helga (vbQN_gmW) (Autodesk Fusion 360 design; units mm, degrees)
Autodesk Fusion 360 part; units mm, degrees
sketch "Sketch1" plane through (0, 0, 0) normal (0, 1, 0) x (1, 0, 0)
  line L0 (-18.8529, -6.608) -> (-18.8529, 6.7072)
  line L1 (-18.8529, 6.7072) -> (-13.5404, 6.7072)
  line L2 (-13.5404, 6.7072) -> (-13.5404, 9.306)
  line L3 (-13.5404, 9.306) -> (-10.8692, 9.306)
  line L4 (-10.8692, 9.306) -> (-10.8692, 14.6796)
  line L5 (-10.8692, 14.6796) -> (-8.1875, 14.6796)
  line L6 (-8.1875, 14.6796) -> (-8.1875, 17.4084)
  line L7 (-8.1875, 17.4084) -> (-2.8745, 17.4084)
  line L8 (-2.8745, 17.4084) -> (-2.8745, 20.1089)
  line L9 (-2.8745, 20.1089) -> (13.211, 20.1089)
  line L10 (13.211, 20.1089) -> (13.211, 17.4084)
  line L11 (21.2891, -9.3556) -> (21.2891, -12.059)
  line L12 (21.2891, -12.059) -> (18.5792, -12.059)
  line L13 (18.5792, -12.059) -> (18.5792, -14.682)
  line L14 (18.5792, -14.682) -> (15.9015, -14.682)
  line L15 (15.9015, -14.682) -> (15.9015, -17.4193)
  line L16 (15.9015, -17.4193) -> (13.2066, -17.4193)
  line L17 (-2.8389, -17.4193) -> (-8.1595, -17.4193)
  line L18 (-10.8692, 9.306) -> (-10.8657, -14.7405)
  line L19 (-18.8529, -6.608) -> (23.8924, -6.608)
  line L20 (-13.5404, 6.7072) -> (-13.5404, -9.665)
  line L21 (21.2891, -9.3556) -> (-13.5404, -9.3556)
  line L22 (18.5792, -12.059) -> (-10.8661, -12.059)
  line L23 (15.9015, -14.682) -> (-15.6391, -14.682)
  line L24 (13.2066, -17.4193) -> (-2.8389, -17.4193)
  line L25 (-8.1875, 14.6796) -> (-8.1875, -20.5391)
  line L26 (21.2891, -9.3556) -> (21.2891, 15.6129)
  line L27 (18.5792, -12.059) -> (18.5792, 18)
  line L28 (-8.1875, 14.6796) -> (23.3304, 14.6796)
  line L29 (-2.8745, 17.4084) -> (23.633, 17.4084)
  line L30 (15.9015, -14.682) -> (15.9015, 21.5634)
  line L31 (13.2066, -17.4193) -> (13.211, 17.4084)
  line L32 (-2.8745, 17.4084) -> (-2.8745, -22)
  line L33 (13.2066, -17.4193) -> (13.2088, -20.0387)
  line L34 (13.2088, -20.0387) -> (-3.2969, -20.0524)
  line L35 (21.2891, -9.3556) -> (23.9084, -9.3556)
  line L36 (-10.8692, 9.306) -> (27.1159, 9.306)
  line L37 (23.9084, -9.3556) -> (23.9084, 10.661)
  line L38 (21.2891, 12.0886) -> (-11.4104, 12.0886)
  line L39 (-13.5404, 6.7072) -> (25.3004, 6.7072)
  line L40 (-18.8529, -3.9765) -> (23.9084, -3.9765)
  line L41 (-16.2077, -1.3461) -> (-18.8529, -1.3461)
  line L42 (-16.2077, -1.3461) -> (25.3213, -1.3461)
  line L43 (-16.166, 1.3788) -> (-18.8529, 1.3788)
  line L44 (-16.166, 1.3788) -> (24.817, 1.3788)
  line L45 (-16.144, 3.9482) -> (-18.8529, 3.9482)
  line L46 (-16.144, 3.9482) -> (24.3622, 3.9482)
  line L47 (-16.144, 3.9482) -> (-16.144, 7.2291)
  line L48 (-16.144, 3.9482) -> (-16.166, -6.9315)
  line L49 (0, 0) -> (0.0167, -20.0497)
  line L50 (0, 0) -> (0, 20.1089)
  line L51 (-5.4992, -17.4193) -> (-5.531, 17.4084)
  line L52 (2.5197, -6.608) -> (2.5309, -20.0476)
  line L53 (2.5197, -6.608) -> (2.5197, 20.1089)
  line L54 (2.5309, -20.0476) -> (5.3487, -20.0452)
  line L55 (5.3487, -20.0452) -> (5.3487, 20.1089)
  line L56 (5.3487, -20.0452) -> (8.2373, -20.0428)
  line L57 (8.2373, -20.0428) -> (8.2373, 20.1089)
  line L58 (10.5159, -3.9765) -> (10.5159, -20.0452)
  line L59 (10.5159, -3.9765) -> (10.5159, 20.1089)
  line L60 (-16.1654, -6.608) -> (-13.5404, -9.3556)
  line L61 (-13.5404, -9.3556) -> (-10.8661, -12.059)
  line L62 (-10.8657, -14.7405) -> (-8.1595, -17.4193)
  line L63 (-5.4992, -17.4193) -> (-5.4989, -17.6947)
  line L64 (-5.4992, -17.4193) -> (-2.8745, -20.0521)
  line L65 (13.2088, -20.0387) -> (15.9015, -17.4193)
  line L66 (15.9015, -17.4193) -> (18.5792, -14.682)
  line L67 (18.5792, -14.682) -> (21.2891, -12.059)
  line L68 (21.2891, -12.059) -> (23.9084, -9.3556)
  line L69 (23.9084, 9.306) -> (21.2891, 12.0886)
  line L70 (21.2891, 12.0886) -> (18.5792, 14.6796)
  line L71 (18.5792, 14.6796) -> (15.9015, 17.4084)
  line L72 (15.9015, 17.4084) -> (13.211, 20.1089)
  line L73 (-2.8745, 20.1089) -> (-5.531, 17.4084)
  line L74 (-8.1875, 17.4084) -> (-10.8692, 14.6796)
  line L75 (-10.8692, 12.0886) -> (-13.5404, 9.306)
  line L76 (-13.5404, 9.306) -> (-16.144, 6.7072)
  dimension "d6" = 31.5406
  constraint vertical L0
  constraint perpendicular L0 L1
  constraint perpendicular L1 L2
  constraint perpendicular L2 L3
  constraint perpendicular L3 L4
  constraint perpendicular L4 L5
  constraint perpendicular L5 L6
  constraint perpendicular L6 L7
  constraint perpendicular L7 L8
  constraint perpendicular L8 L9
  constraint perpendicular L9 L10
  constraint perpendicular L11 L12
  constraint perpendicular L12 L13
  constraint perpendicular L13 L14
  constraint perpendicular L14 L15
  constraint perpendicular L15 L16
  constraint perpendicular L19 L20
  constraint coincident L20 L21.end
  constraint perpendicular L20 L21
  constraint coincident L18 L22.end
  constraint perpendicular L13 L22
  constraint horizontal L23
  constraint perpendicular L17 L25
  constraint perpendicular L21 L26
  constraint perpendicular L26 L28
  constraint perpendicular L27 L29
  constraint perpendicular L29 L30
  constraint perpendicular L33 L34
  constraint perpendicular L26 L35
  constraint horizontal L36
  constraint perpendicular L36 L37
  constraint coincident L26 L38.start
  constraint perpendicular L4 L38
  constraint perpendicular L37 L39
  constraint coincident L0 L40.start
  constraint coincident L37 L40.end
  constraint perpendicular L37 L40
  constraint coincident L0 L41.end
  constraint perpendicular L0 L41
  constraint perpendicular L37 L42
  constraint coincident L0 L43.end
  constraint perpendicular L0 L43
  constraint perpendicular L37 L44
  constraint coincident L0 L45.end
  constraint perpendicular L0 L45
  constraint perpendicular L37 L46
  constraint perpendicular L1 L47
  constraint coincident L49.start L50.start
  constraint coincident L34 L49.end
  constraint perpendicular L34 L49
  constraint coincident L9 L50.end
  constraint perpendicular L9 L50
  constraint midpoint L17 L51.start
  constraint midpoint L7 L51.end
  constraint midpoint L19 L52.start
  constraint coincident L34 L52.end
  constraint perpendicular L34 L52
  constraint coincident L9 L53.end
  constraint perpendicular L9 L53
  constraint coincident L34 L54.end
  constraint coincident L9 L55.end
  constraint perpendicular L9 L55
  constraint coincident L34 L56.end
  constraint parallel L34 L56
  constraint coincident L9 L57.end
  constraint perpendicular L9 L57
  constraint coincident L40 L58.start
  constraint perpendicular L24 L58
  constraint coincident L9 L59.end
  constraint perpendicular L9 L59
  constraint coincident L48 L60.start
  constraint coincident L19 L60.start
  constraint coincident L34 L64.end
  constraint coincident L32 L64.end
  constraint coincident L36 L69.start
  constraint coincident L37 L69.start
  constraint coincident L28 L70.end
  constraint coincident L27 L70.end
  constraint coincident L30 L71.end
  constraint coincident L29 L71.end
  constraint coincident L4 L75.start
  constraint coincident L38 L75.start
  constraint coincident L47 L76.end
  constraint coincident L1 L76.end
  measures "d6" distance of L14.end L23.end
extrude "Extrude1" add sketch "Sketch1" along normal blind 4 contours L20 L40 L42 L48 | L18 L20 L40 L42 | L18 L19 L21 L25 | L18 L19 L25 L40 | L18 L25 L40 L42 | L20 L44 L46 L48 | L19 L25 L40 L51 | L19 L21 L25 L51 | L21 L22 L25 L51 | L22 L23 L25 L51 | L18 L20 L44 L46 | L18 L25 L42 L44 | L25 L40 L42 L51 | L19 L32 L40 L51 | L19 L21 L32 L51 | L21 L22 L32 L51 | L22 L23 L32 L51 | L18 L25 L44 L46 | L25 L42 L44 L51 | L32 L40 L42 L51 | L19 L32 L40 L49 | L19 L21 L32 L49 | L21 L22 L32 L49 | L22 L23 L32 L49 | L18 L25 L39 L46 | L25 L44 L46 L51 | L32 L42 L44 L51 | L32 L40 L42 L49 | L19 L40 L49 L53 | L19 L21 L49 L52 | L21 L22 L49 L52 | L17 L23 L24 L32 L49 | L22 L23 L49 L52 | L18 L25 L36 L39 | L25 L39 L46 L51 | L32 L44 L46 L51 | L32 L42 L44 L49 L50 | L19 L21 L52 L55 | L21 L22 L52 L55 | L23 L24 L49 L52 | L22 L23 L52 L55 | L25 L36 L39 L51 | L25 L36 L38 L51 | L25 L28 L38 L51 | L32 L39 L46 L51 | L32 L44 L46 L50 | L19 L21 L55 L57 | L21 L22 L55 L57 | L23 L24 L52 L55 | L22 L23 L55 L57 | L32 L36 L39 L51 | L32 L36 L38 L51 | L28 L32 L38 L51 | L32 L39 L46 L50 | L19 L21 L57 L58 | L21 L22 L57 L58 | L23 L24 L55 L57 | L22 L23 L57 L58 | L32 L36 L39 L50 | L32 L36 L38 L50 | L28 L32 L38 L50 | L39 L46 L50 L53 | L23 L24 L57 L58 | L22 L23 L31 L58 | L36 L39 L50 L53 | L36 L38 L50 L53 | L28 L29 L32 L50 | L28 L38 L50 L53 | L19 L21 L30 L31 | L21 L22 L30 L31 | L23 L24 L31 L58 | L22 L23 L30 L31 | L36 L39 L53 L55 | L36 L38 L53 L55 | L28 L29 L50 L53 | L28 L38 L53 L55 | L19 L27 L30 L40 | L19 L21 L27 L30 | L21 L22 L27 L30 | L36 L39 L55 L57 | L36 L38 L55 L57 | L28 L29 L53 L55 | L28 L38 L55 L57 | L27 L30 L40 L42 | L19 L26 L27 L40 | L19 L21 L26 L27 | L36 L39 L57 L59 | L36 L38 L57 L59 | L28 L29 L55 L57 | L28 L38 L57 L59 | L27 L30 L42 L44 | L26 L27 L40 L42 | L28 L29 L57 L59 | L28 L31 L38 L59 | L27 L30 L44 L46 | L26 L27 L42 L44 | L30 L31 L36 L39 | L30 L31 L36 L38 | L28 L29 L31 L59 | L28 L30 L31 L38 | L27 L30 L39 L46 | L26 L27 L44 L46 | L27 L30 L36 L39 | L27 L30 L36 L38 | L26 L27 L39 L46 | L26 L27 L36 L39
chamfer "Chamfer1" distance 0.7 angle 45 49 edges at (-9.527, 4, 9.3556) (-8.1875, 4, 12.0188) (-5.531, 4, 14.682) (5.1661, 4, 17.4193) (-2.8745, 4, 16.0506) (13.2068, 4, 16.0506) (14.5542, 4, 14.682) (15.9015, 4, 13.3705) (17.2404, 4, 12.059) (18.5792, 4, 10.7073) (19.9341, 4, 9.3556) (21.2891, 4, 0.0248) (19.9341, 4, -9.306) (18.5792, 4, -10.6973) (17.2404, 4, -12.0886) (15.9015, 4, -13.3841) (14.5561, 4, -14.6796) (13.2108, 4, -16.044) (5.1683, 4, -17.4084) (-2.8745, 4, -16.044) (-5.531, 4, -14.6796) (-8.1875, 4, -11.9928) (-9.5283, 4, -9.306) (-10.8688, 4, -6.6271) (-13.5062, 4, -3.9482) (-13.5086, 4, -1.3788) (-16.1466, 4, -2.6635) (-10.8678, 4, -0.0164) (-13.5112, 4, 1.3461) (-16.1574, 4, 2.6613) (-13.5136, 4, 3.9765) (-10.8669, 4, 6.6661) (0.0017, 4, 1.9883) (0, 4, -1.9741) (1.2615, 4, 3.9765) (2.5197, 4, 5.2922) (6.5178, 4, 6.608) (10.5159, 4, 9.3335) (11.8616, 4, 12.059) (13.2076, 4, 9.3335) (14.5547, 4, 6.608) (15.9015, 4, -0.0496) (14.5556, 4, -6.7072) (13.21, 4, -9.3979) (11.8631, 4, -12.0886) (10.5159, 4, -9.3979) (6.5178, 4, -6.7072) (2.5197, 4, -5.3277) (1.2599, 4, -3.9482) tangent chain off
